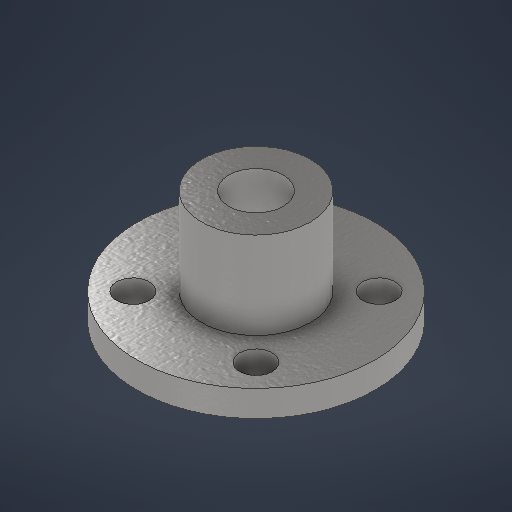
# Autodesk Inventor part: 5_Co
Saved by Autodesk Inventor 2026.2 (Build 302298010, 298A)
## iProperties
Created: 2026-03-19
Part Number: 5_Co
Material: 스테인리스스틸
Document SubType Name: Modeling
Designer: work
Density: 8 g/cm^3
Appearance: 아연도금
Mass: 10.0186 g
Surface Area: 13.3747 cm^2
Volume: 1.25232 cm^3
Author: work
Autodesk Inventor part; units mm, degrees
ref_plane "YZ Plane" through (0, 0, 0) normal (1, 0, 0) x (0, 1, 0)
ref_plane "XZ Plane" through (0, 0, 0) normal (0, 1, 0) x (-1, 0, 0)
ref_plane "XY Plane" through (0, 0, 0) normal (0, 0, 1) x (1, 0, 0)
sketch "스케치1" plane through (0, 0, 0) normal (0, 0, 1) x (1, 0, 0)
  line L0 (0, 0) -> (0, 10.4)
  line L1 (2.5, 0) -> (2.5, 10.4)
  line L2 (2.5, 10.4) -> (5, 10.4)
  line L3 (5, 10.4) -> (5, 2.4)
  line L4 (5, 2.4) -> (10.95, 2.4)
  line L5 (10.95, 2.4) -> (10.95, 0)
  line L6 (2.5, 0) -> (10.95, 0)
  line L7 (2.5, 0) -> (0, 0) construction
  point P0 (10.95, 1.2)
  dimension "d0" = 10.4
  dimension "d1" = 2.4
  dimension "d2" = 10
  dimension "d3" = 5
  dimension "d4" = 10.4
  dimension "d5" = 21.9
  constraints: 16 end point, 6 perpendicular, 2 vertical, 1 midpoint
  measures "d0" distance of L0.start L0.end
  measures "d1" distance between parallel lines of L4 L6
  measures "d2" diameter of L3 L0
  measures "d3" diameter of L1 L0
  measures "d4" distance from line of L0.start L2
  measures "d5" diameter of point (10.95, 1.2) L0
revolve "회전1" add sketch "스케치1" angle 360 about axis through (0, 0, 0) along (0, 1, 0)
sketch "스케치2" plane through (0, 2.4, 0) normal (0, 1, 0) x (1, 0, 0)
  circle A0 centre (0, 0) radius 8 construction
  line L0 (5.6569, -5.6569) -> (-5.6569, -5.6569) construction
  line L1 (-5.6569, -5.6569) -> (-5.6569, 5.6569) construction
  line L2 (-5.6569, 5.6569) -> (5.6569, 5.6569) construction
  line L3 (5.6569, 5.6569) -> (5.6569, -5.6569) construction
  line L4 (5.6569, -5.6569) -> (-5.6569, 5.6569) construction
  line L5 (-5.6569, -5.6569) -> (5.6569, 5.6569) construction
  point P0 (5.6569, -5.6569)
  point P1 (-5.6569, 5.6569)
  dimension "d7" = 16
  constraints: 12 end point, 4 coincident, 2 midpoint, 2 parallel, 2 perpendicular, 2 point on circle, 1 centre point, 1 horizontal
  measures "d7" diameter of A0
hole "구멍1" at (-5.6569, 2.4, 5.6569) at (5.6569, 2.4, 5.6569) at (5.6569, 2.4, -5.6569) at (-5.6569, 2.4, -5.6569) direction (0, -1, 0) diameter 3 end through all
sketch "스케치3" plane through (0, 0, 0) normal (1, 0, 0) x (0, 1, 0)
  line L0 (10.4, -2.5) -> (10.4, 2.5) projected
  line L1 (10.4, 0) -> (6.4, 0) construction
  circle A0 centre (6.4, 0) radius 1
  point P0 (0, 0)
  dimension "d15" = 4
  dimension "d16" = 2
  constraints: 2 end point, 1 centre point, 1 coincident, 1 horizontal, 1 midpoint
  measures "d15" distance of L1.start L1.end
  measures "d16" diameter of A0
extrude "돌출1" cut sketch "스케치3" against normal blind 10
